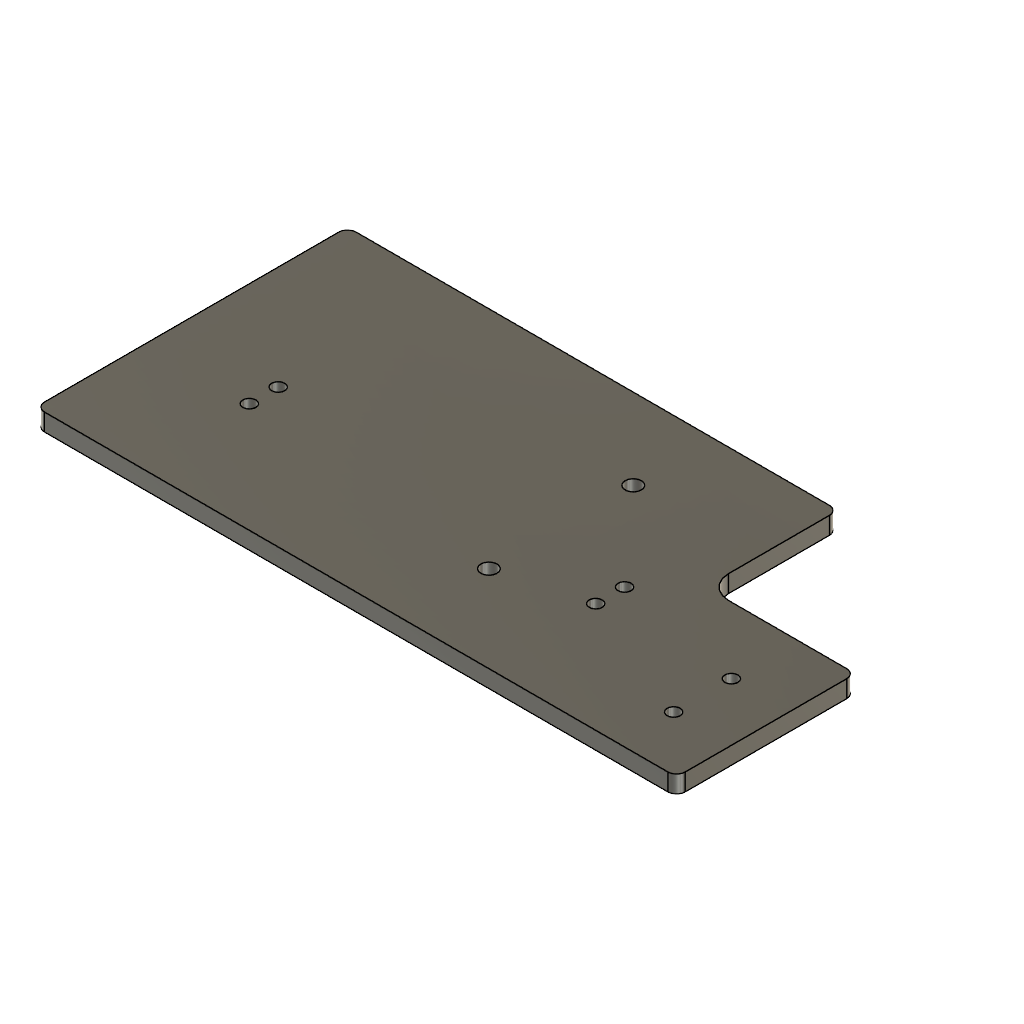
VISION_SWINE_Mounting_Plate_V3 (Autodesk Fusion 360 design; units mm, degrees)
part number: 2026-11-26-04-38-50-529
part number: 2026-11-26-04-38-50-947
Autodesk Fusion 360 part; units mm, degrees
ref_plane "WorkPlane1" through (-30, 0, 0) normal (1, 0, 0) x (0, 1, 0) in component "Mounting_Plate_V3"
ref_plane "WorkPlane2" through (0, -10, 0) normal (0, 1, 0) x (0, 0, 1) in component "Mounting_Plate_V3"
ref_plane "WorkPlane3" through (192, 0, 0) normal (1, 0, 0) x (0, 1, 0) in component "Mounting_Plate_V3"
ref_plane "WorkPlane4" through (0, 52, 0) normal (0, 1, 0) x (0, 0, 1) in component "Mounting_Plate_V3"
ref_plane "WorkPlane5" through (140, 0, 0) normal (1, 0, 0) x (0, 1, 0) in component "Mounting_Plate_V3"
ref_plane "WorkPlane6" through (0, 98, 0) normal (0, 1, 0) x (0, 0, 1) in component "Mounting_Plate_V3"
sketch "Main plate and camera tongue" plane through (0, 0, 0) normal (0, 0, 1) x (1, 0, 0) in component "Mounting_Plate_V3"
  line L0 (-30, -10) -> (192, -10)
  line L1 (192, -10) -> (192, 52)
  line L2 (192, 52) -> (140, 52)
  line L3 (140, 52) -> (140, 98)
  line L4 (140, 98) -> (-30, 98)
  line L5 (-30, 98) -> (-30, -10)
extrude "Plate blank" add sketch "Main plate and camera tongue" along normal blind 6 in component "Mounting_Plate_V3"
fillet "Outside and tongue root radii" radius 8 1 edges at (140, 52, 3) in component "Mounting_Plate_V3"
fillet "Outside and tongue root radii" radius 3 5 edges at (-30, -10, 3) (192, -10, 3) (192, 52, 3) (140, 98, 3) (-30, 98, 3) in component "Mounting_Plate_V3"
ref_plane "WorkPlane7" through (6, 0, 0) normal (1, 0, 0) x (0, 1, 0) in component "Mounting_Plate_V3"
ref_plane "WorkPlane8" through (0, 38, 0) normal (0, 1, 0) x (0, 0, 1) in component "Mounting_Plate_V3"
sketch "Sketch2" plane through (0, 0, 0) normal (0, 0, 1) x (1, 0, 0) in component "Mounting_Plate_V3"
  circle A0 centre (6, 38) radius 2.25
  dimension "d45" = 4.5
  measures "d45" diameter of A0
extrude "M4 clearance 1" cut sketch "Sketch2" along normal blind 6 in component "Mounting_Plate_V3"
ref_plane "WorkPlane9" through (6, 0, 0) normal (1, 0, 0) x (0, 1, 0) in component "Mounting_Plate_V3"
ref_plane "WorkPlane10" through (0, 28, 0) normal (0, 1, 0) x (0, 0, 1) in component "Mounting_Plate_V3"
sketch "Sketch3" plane through (0, 0, 0) normal (0, 0, 1) x (1, 0, 0) in component "Mounting_Plate_V3"
  circle A0 centre (6, 28) radius 2.25
  dimension "d52" = 4.5
  measures "d52" diameter of A0
extrude "M4 clearance 2" cut sketch "Sketch3" along normal blind 6 in component "Mounting_Plate_V3"
ref_plane "WorkPlane11" through (126, 0, 0) normal (1, 0, 0) x (0, 1, 0) in component "Mounting_Plate_V3"
ref_plane "WorkPlane12" through (0, 38, 0) normal (0, 1, 0) x (0, 0, 1) in component "Mounting_Plate_V3"
sketch "Sketch4" plane through (0, 0, 0) normal (0, 0, 1) x (1, 0, 0) in component "Mounting_Plate_V3"
  circle A0 centre (126, 38) radius 2.25
  dimension "d59" = 4.5
  measures "d59" diameter of A0
extrude "M4 clearance 3" cut sketch "Sketch4" along normal blind 6 in component "Mounting_Plate_V3"
ref_plane "WorkPlane13" through (126, 0, 0) normal (1, 0, 0) x (0, 1, 0) in component "Mounting_Plate_V3"
ref_plane "WorkPlane14" through (0, 28, 0) normal (0, 1, 0) x (0, 0, 1) in component "Mounting_Plate_V3"
sketch "Sketch5" plane through (0, 0, 0) normal (0, 0, 1) x (1, 0, 0) in component "Mounting_Plate_V3"
  circle A0 centre (126, 28) radius 2.25
  dimension "d66" = 4.5
  measures "d66" diameter of A0
extrude "M4 clearance 4" cut sketch "Sketch5" along normal blind 6 in component "Mounting_Plate_V3"
ref_plane "WorkPlane15" through (172, 0, 0) normal (1, 0, 0) x (0, 1, 0) in component "Mounting_Plate_V3"
ref_plane "WorkPlane16" through (0, 9, 0) normal (0, 1, 0) x (0, 0, 1) in component "Mounting_Plate_V3"
sketch "Sketch6" plane through (0, 0, 0) normal (0, 0, 1) x (1, 0, 0) in component "Mounting_Plate_V3"
  circle A0 centre (172, 9) radius 2.25
  dimension "d73" = 4.5
  measures "d73" diameter of A0
extrude "M4 clearance 5" cut sketch "Sketch6" along normal blind 6 in component "Mounting_Plate_V3"
ref_plane "WorkPlane17" through (172, 0, 0) normal (1, 0, 0) x (0, 1, 0) in component "Mounting_Plate_V3"
ref_plane "WorkPlane18" through (0, 29, 0) normal (0, 1, 0) x (0, 0, 1) in component "Mounting_Plate_V3"
sketch "Sketch7" plane through (0, 0, 0) normal (0, 0, 1) x (1, 0, 0) in component "Mounting_Plate_V3"
  circle A0 centre (172, 29) radius 2.25
  dimension "d80" = 4.5
  measures "d80" diameter of A0
extrude "M4 clearance 6" cut sketch "Sketch7" along normal blind 6 in component "Mounting_Plate_V3"
ref_plane "WorkPlane19" through (0, 0, 6) normal (0, 0, 1) x (1, 0, 0) in component "Mounting_Plate_V3"
ref_plane "WorkPlane20" through (97, 0, 0) normal (1, 0, 0) x (0, 1, 0) in component "Mounting_Plate_V3"
ref_plane "WorkPlane21" through (0, 20, 0) normal (0, 1, 0) x (0, 0, 1) in component "Mounting_Plate_V3"
sketch "Sketch8" plane through (0, 0, 6) normal (0, 0, 1) x (1, 0, 0) in component "Mounting_Plate_V3"
  circle A0 centre (97, 20) radius 2.8
  dimension "d94" = 5.6
  measures "d94" diameter of A0
extrude "Blind M4 insert seat -" cut sketch "Sketch8" against normal blind 4.5 in component "Mounting_Plate_V3"
ref_plane "WorkPlane22" through (0, 70, 0) normal (0, 1, 0) x (0, 0, 1) in component "Mounting_Plate_V3"
sketch "Sketch9" plane through (0, 0, 6) normal (0, 0, 1) x (1, 0, 0) in component "Mounting_Plate_V3"
  circle A0 centre (97, 70) radius 2.8
  dimension "d99" = 5.6
  measures "d99" diameter of A0
extrude "Blind M4 insert seat +" cut sketch "Sketch9" against normal blind 4.5 in component "Mounting_Plate_V3"
component "Mounting_Plate_V3" placed x (1, 0, 0) y (0, 1, 0) z (0, 0, 1) at (0, 0, 0)
equation "mp2X = -30 mm" comment "Mounting Plate V2"
equation "mp2Y = -10 mm" comment "Mounting Plate V2"
equation "mp2MainW = 170 mm" comment "Mounting Plate V2"
equation "mp2MainH = 108 mm" comment "Mounting Plate V2"
equation "mp2Reach = 52 mm" comment "Mounting Plate V2"
equation "mp2TongueW = 62 mm" comment "Mounting Plate V2"
equation "mp2T = 6 mm" comment "Mounting Plate V2"
equation "mp2OuterR = 3 mm" comment "Mounting Plate V2"
equation "mp2RootR = 8 mm" comment "Mounting Plate V2"
equation "mp2HoleD = 4.5 mm" comment "Mounting Plate V2"
equation "mp2Hole1X = 6.000000 mm" comment "Mounting Plate V2"
equation "mp2Hole1Y = 38.000000 mm" comment "Mounting Plate V2"
equation "mp2Hole2X = 6.000000 mm" comment "Mounting Plate V2"
equation "mp2Hole2Y = 28.000000 mm" comment "Mounting Plate V2"
equation "mp2Hole3X = 126.000000 mm" comment "Mounting Plate V2"
equation "mp2Hole3Y = 38.000000 mm" comment "Mounting Plate V2"
equation "mp2Hole4X = 126.000000 mm" comment "Mounting Plate V2"
equation "mp2Hole4Y = 28.000000 mm" comment "Mounting Plate V2"
equation "mp2Hole5X = 172.000000 mm" comment "Mounting Plate V2"
equation "mp2Hole5Y = 9.000000 mm" comment "Mounting Plate V2"
equation "mp2Hole6X = 172.000000 mm" comment "Mounting Plate V2"
equation "mp2Hole6Y = 29.000000 mm" comment "Mounting Plate V2"
equation "d23 = mp2X"
equation "d25 = mp2Y"
equation "d27 = mp2X + mp2MainW + mp2Reach"
equation "d29 = mp2Y + mp2TongueW"
equation "d31 = mp2X + mp2MainW"
equation "d33 = mp2Y + mp2MainH"
equation "d35 = mp2T"
equation "d38 = mp2RootR"
equation "d40 = mp2OuterR"
equation "d41 = mp2Hole1X"
equation "d43 = mp2Hole1Y"
equation "d45 = mp2HoleD"
equation "d46 = mp2T"
equation "d48 = mp2Hole2X"
equation "d50 = mp2Hole2Y"
equation "d52 = mp2HoleD"
equation "d53 = mp2T"
equation "d55 = mp2Hole3X"
equation "d57 = mp2Hole3Y"
equation "d59 = mp2HoleD"
equation "d60 = mp2T"
equation "d62 = mp2Hole4X"
equation "d64 = mp2Hole4Y"
equation "d66 = mp2HoleD"
equation "d67 = mp2T"
equation "d69 = mp2Hole5X"
equation "d71 = mp2Hole5Y"
equation "d73 = mp2HoleD"
equation "d74 = mp2T"
equation "d76 = mp2Hole6X"
equation "d78 = mp2Hole6Y"
equation "d80 = mp2HoleD"
equation "d81 = mp2T"
equation "mp3X = 97 mm" comment "Central M4 insert trial"
equation "mp3Y = 45 mm" comment "Central M4 insert trial"
equation "mp3Pitch = 50 mm" comment "Central M4 insert trial"
equation "mp3PilotD = 5.6 mm" comment "Central M4 insert trial"
equation "mp3Pocket = 4.5 mm" comment "Central M4 insert trial"
equation "d88 = mp2T"
equation "d90 = mp3X"
equation "d92 = mp3Y - mp3Pitch / 2"
equation "d94 = mp3PilotD"
equation "d95 = -( mp3Pocket )"
equation "d97 = mp3Y + mp3Pitch / 2"
equation "d99 = mp3PilotD"
equation "d100 = -( mp3Pocket )"
named bodies: "Mounting Plate V3"
